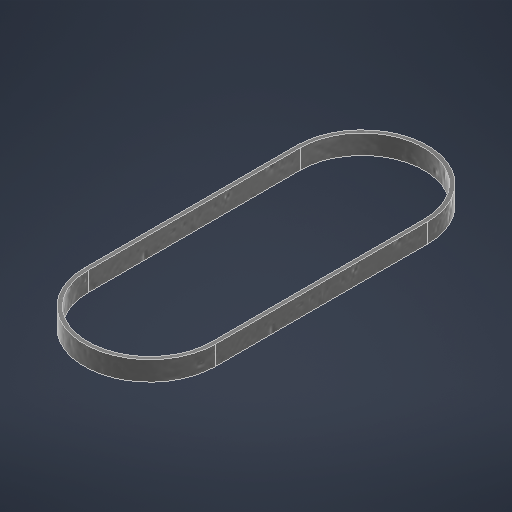
# Autodesk Inventor part: timing_belt
Saved by Autodesk Inventor 2027.1 (Build 311270010, 270A)
## iProperties
Created: 2026-10-09
Part Number: timing_belt
Material: Generic
Document SubType Name: Modeling
Designer: lucao
Density: 1 g/cm^3
Appearance: Fine Textured - Black
Author: lucao
Autodesk Inventor part; units mm, degrees
ref_plane "YZ Plane" through (0, 0, 0) normal (1, 0, 0) x (0, 1, 0)
ref_plane "XZ Plane" through (0, 0, 0) normal (0, 1, 0) x (-1, 0, 0)
ref_plane "XY Plane" through (0, 0, 0) normal (0, 0, 1) x (1, 0, 0)
sketch "Sketch1" plane through (0, 0, 0) normal (0, 1, 0) x (-1, 0, 0)
  arc A0 (20.3, 0) -> (-20.3, 0) centre (0, 0) ccw
  arc A1 (-20.3, -65.5) -> (20.3, -65.5) centre (0, -65.5) ccw
  line L0 (20.3, 0) -> (20.3, -65.5)
  line L1 (-20.3, -65.5) -> (-20.3, 0)
  line L2 (19.1, -65.5) -> (19.1, 0)
  arc A2 (19.1, 0) -> (-19.1, 0) centre (0, 0) ccw
  line L3 (-19.1, 0) -> (-19.1, -65.5)
  arc A3 (-19.1, -65.5) -> (19.1, -65.5) centre (0, -65.5) ccw
  dimension "d2" = 65.5
  dimension "d3" = 1.2
  dimension "d6" = 19.1
  dimension "d7" = 19.1
  constraints: 8 end point, 8 point on circle, 4 centre point, 3 tangent, 1 coincident, 1 vertical, 1 vertical alignment, 3 other
  measures "d2" distance of A1.centre point (0, 0)
  measures "d3" distance between parallel lines of L0 L2
  measures "d6" radius of A2
  measures "d7" radius of A3
extrude "Extrusion1" add sketch "Sketch1" along normal blind 6
equation "\"d7\" = d6"
body "Solid1"
